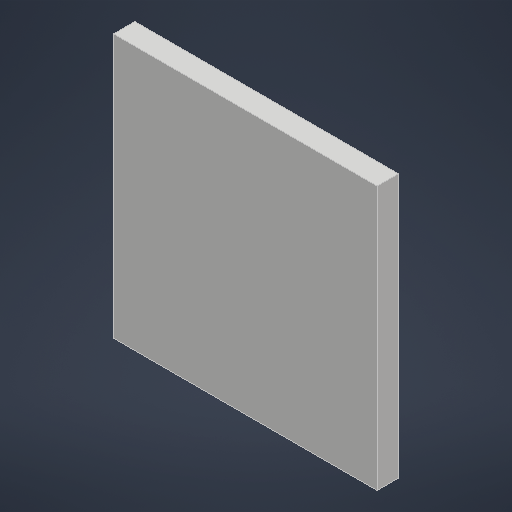
# Autodesk Inventor part: Marble Maze Template
Saved by Autodesk Inventor 2027 (Build 310192060, 192F)
## iProperties
Created: 2021-01-22
Part Number: Marble Maze Template
Material: Generic
Document SubType Name: Modeling
Designer: ScottSt
Density: 1 g/cm^3
Appearance: Default
Author: ScottSt
Autodesk Inventor part; units mm, degrees
ref_plane "YZ Plane" through (0, 0, 0) normal (1, 0, 0) x (0, 1, 0)
ref_plane "XZ Plane" through (0, 0, 0) normal (0, 1, 0) x (-1, 0, 0)
ref_plane "XY Plane" through (0, 0, 0) normal (0, 0, 1) x (1, 0, 0)
sketch "Sketch1" plane through (0, 0, 0) normal (0, 1, 0) x (-1, 0, 0)
  line L0 (83.5, -83.5) -> (-83.5, -83.5)
  line L1 (-83.5, -83.5) -> (-83.5, 83.5)
  line L2 (-83.5, 83.5) -> (83.5, 83.5)
  line L3 (83.5, 83.5) -> (83.5, -83.5)
  line L4 (83.5, -83.5) -> (-83.5, 83.5) construction
  line L5 (-83.5, -83.5) -> (83.5, 83.5) construction
  point P0 (0, 0)
  dimension "d6" = 167
  dimension "d7" = 167
  constraints: 12 end point, 2 midpoint, 2 parallel, 1 horizontal, 1 perpendicular
  measures "d6" distance of L1.end L2.end
  measures "d7" distance of L0.end L1.end
extrude "Extrusion3" add sketch "Sketch1" along normal blind 3.5
sketch "Maze Layout" plane through (0, 3.5, 0) normal (0, 1, 0) x (1, 0, 0)
  line L0 (83.5, 83.5) -> (-83.5, 83.5) construction
  line L1 (83.5, -83.5) -> (83.5, 83.5) construction
  line L2 (-83.5, 83.5) -> (83.5, 83.5) construction
  line L3 (83.5, 83.5) -> (83.5, -83.5) construction
  line L4 (-80.5, -80.5) -> (80.5, -80.5) construction
  line L5 (80.5, -80.5) -> (80.5, 80.5) construction
  line L6 (80.5, 80.5) -> (-80.5, 80.5) construction
  line L7 (-80.5, 80.5) -> (-80.5, -80.5) construction
  line L8 (-80.5, -80.5) -> (-83.5, -80.5) construction
  line L9 (-83.5, -80.5) -> (-80.5, -80.5) construction
  line L10 (-80.5, -80.5) -> (-80.5, -83.5) construction
  line L11 (-83.5, -80.5) -> (-83.5, 80.5) construction
  line L12 (-83.5, 83.5) -> (-83.5, -83.5) construction
  line L13 (-83.5, 80.5) -> (-80.5, 80.5) construction
  line L14 (-60, 80.5) -> (-60, -80.5) construction
  line L15 (-63, -80.5) -> (-63, 80.5) construction
  line L16 (-63, 80.5) -> (-60, 80.5) construction
  line L17 (-60, -80.5) -> (-63, -80.5) construction
  line L18 (-39.5, 80.5) -> (-39.5, -80.5) construction
  line L19 (-42.5, -80.5) -> (-42.5, 80.5) construction
  line L20 (-42.5, 80.5) -> (-39.5, 80.5) construction
  line L21 (-39.5, -80.5) -> (-42.5, -80.5) construction
  line L22 (-19, 80.5) -> (-19, -80.5) construction
  line L23 (-22, -80.5) -> (-22, 80.5) construction
  line L24 (-22, 80.5) -> (-19, 80.5) construction
  line L25 (-19, -80.5) -> (-22, -80.5) construction
  line L26 (1.5, 80.5) -> (1.5, -80.5) construction
  line L27 (-1.5, -80.5) -> (-1.5, 80.5) construction
  line L28 (-1.5, 80.5) -> (1.5, 80.5) construction
  line L29 (1.5, -80.5) -> (-1.5, -80.5) construction
  line L30 (22, 80.5) -> (22, -80.5) construction
  line L31 (19, -80.5) -> (19, 80.5) construction
  line L32 (19, 80.5) -> (22, 80.5) construction
  line L33 (22, -80.5) -> (19, -80.5) construction
  line L34 (42.5, 80.5) -> (42.5, -80.5) construction
  line L35 (39.5, -80.5) -> (39.5, 80.5) construction
  line L36 (39.5, 80.5) -> (42.5, 80.5) construction
  line L37 (42.5, -80.5) -> (39.5, -80.5) construction
  line L38 (63, 80.5) -> (63, -80.5) construction
  line L39 (60, -80.5) -> (60, 80.5) construction
  line L40 (60, 80.5) -> (63, 80.5) construction
  line L41 (63, -80.5) -> (60, -80.5) construction
  line L42 (-80.5, -83.5) -> (80.5, -83.5) construction
  line L43 (80.5, -83.5) -> (80.5, -80.5) construction
  line L44 (-80.5, -60) -> (-80.5, -63) construction
  line L45 (-80.5, -60) -> (80.5, -60) construction
  line L46 (-80.5, -63) -> (80.5, -63) construction
  line L47 (80.5, -63) -> (80.5, -60) construction
  line L48 (-80.5, -39.5) -> (-80.5, -42.5) construction
  line L49 (-80.5, -39.5) -> (80.5, -39.5) construction
  line L50 (-80.5, -42.5) -> (80.5, -42.5) construction
  line L51 (80.5, -42.5) -> (80.5, -39.5) construction
  line L52 (-80.5, -19) -> (-80.5, -22) construction
  line L53 (-80.5, -19) -> (80.5, -19) construction
  line L54 (-80.5, -22) -> (80.5, -22) construction
  line L55 (80.5, -22) -> (80.5, -19) construction
  line L56 (-80.5, 1.5) -> (-80.5, -1.5) construction
  line L57 (-80.5, 1.5) -> (80.5, 1.5) construction
  line L58 (-80.5, -1.5) -> (80.5, -1.5) construction
  line L59 (80.5, -1.5) -> (80.5, 1.5) construction
  line L60 (-80.5, 22) -> (-80.5, 19) construction
  line L61 (-80.5, 22) -> (80.5, 22) construction
  line L62 (-80.5, 19) -> (80.5, 19) construction
  line L63 (80.5, 19) -> (80.5, 22) construction
  line L64 (-80.5, 42.5) -> (-80.5, 39.5) construction
  line L65 (-80.5, 42.5) -> (80.5, 42.5) construction
  line L66 (-80.5, 39.5) -> (80.5, 39.5) construction
  line L67 (80.5, 39.5) -> (80.5, 42.5) construction
  line L68 (-80.5, 63) -> (-80.5, 60) construction
  line L69 (-80.5, 63) -> (80.5, 63) construction
  line L70 (-80.5, 60) -> (80.5, 60) construction
  line L71 (80.5, 60) -> (80.5, 63) construction
  line L72 (42.5, 80.5) -> (39.5, 80.5)
  line L73 (22, 80.5) -> (19, 80.5)
  line L74 (-22, 80.5) -> (-19, 80.5)
  line L75 (-80.5, 60) -> (-80.5, 63)
  line L76 (80.5, 60) -> (80.5, 63)
  line L77 (80.5, 1.5) -> (80.5, -1.5)
  line L78 (63, -80.5) -> (60, -80.5)
  line L79 (22, -80.5) -> (19, -80.5)
  line L80 (-39.5, -80.5) -> (-42.5, -80.5)
  line L81 (-80.5, -60) -> (-80.5, -63)
  line L82 (-80.5, -19) -> (-80.5, -22)
  line L83 (83.5, -83.5) -> (-83.5, -83.5)
  line L84 (-83.5, -83.5) -> (-83.5, 83.5)
  line L85 (-83.5, 83.5) -> (83.5, 83.5)
  line L86 (83.5, 83.5) -> (83.5, -83.5)
  line L87 (-80.5, 80.5) -> (80.5, 80.5)
  line L88 (80.5, 80.5) -> (80.5, -80.5)
  line L89 (80.5, -80.5) -> (-80.5, -80.5)
  line L90 (-80.5, -80.5) -> (-80.5, 80.5)
  line L91 (-80.5, -60) -> (-63, -60)
  line L92 (-63, -60) -> (-63, -42.5)
  line L93 (-63, -42.5) -> (-63, -39.5)
  line L94 (-63, -39.5) -> (-63, 1.5)
  line L95 (-63, 1.5) -> (-39.5, 1.5)
  line L96 (-39.5, 1.5) -> (-39.5, -63)
  line L97 (-39.5, -63) -> (-42.5, -63)
  line L98 (-42.5, -63) -> (-42.5, -1.5)
  line L99 (-42.5, -1.5) -> (-60, -1.5)
  line L100 (-60, -1.5) -> (-60, -63)
  line L101 (-60, -63) -> (-80.5, -63)
  line L102 (-80.5, -63) -> (-80.5, -60)
  line L103 (-22, -63) -> (22, -63)
  line L104 (22, -63) -> (22, -60)
  line L105 (22, -60) -> (-22, -60)
  line L106 (-22, -63) -> (-22, -60)
  line L107 (19, -63) -> (19, -80.5)
  line L108 (19, -80.5) -> (22, -80.5)
  line L109 (22, -80.5) -> (22, -63)
  line L110 (-22, -42.5) -> (39.5, -42.5)
  line L111 (39.5, -42.5) -> (39.5, -63)
  line L112 (39.5, -63) -> (63, -63)
  line L113 (63, -63) -> (63, 1.5)
  line L114 (63, 1.5) -> (1.5, 1.5)
  line L115 (1.5, 1.5) -> (1.5, 19)
  line L116 (1.5, 22) -> (1.5, 19)
  line L117 (1.5, 22) -> (-19, 22)
  line L118 (-19, 39.5) -> (39.5, 39.5)
  line L119 (39.5, 39.5) -> (39.5, 19)
  line L120 (39.5, 19) -> (63, 19)
  line L121 (63, 19) -> (63, 80.5)
  line L122 (63, 80.5) -> (60, 80.5)
  line L123 (60, 80.5) -> (60, 22)
  line L124 (60, 22) -> (42.5, 22)
  line L125 (42.5, 22) -> (42.5, 42.5)
  line L126 (42.5, 42.5) -> (-22, 42.5)
  line L127 (-22, 19) -> (-1.5, 19)
  line L128 (-1.5, 19) -> (-1.5, -1.5)
  line L129 (-1.5, -1.5) -> (60, -1.5)
  line L130 (60, -1.5) -> (60, -60)
  line L131 (60, -60) -> (42.5, -60)
  line L132 (42.5, -60) -> (42.5, -39.5)
  line L133 (42.5, -39.5) -> (-22, -39.5)
  line L134 (-22, -39.5) -> (-22, -42.5)
  line L135 (-1.5, -39.5) -> (-1.5, -22)
  line L136 (-1.5, -22) -> (1.5, -22)
  line L137 (1.5, -22) -> (1.5, -39.5)
  line L138 (19, -1.5) -> (19, -19)
  line L139 (19, -19) -> (22, -19)
  line L140 (22, -19) -> (22, -1.5)
  line L141 (39.5, -39.5) -> (39.5, -22)
  line L142 (39.5, -22) -> (42.5, -22)
  line L143 (42.5, -22) -> (42.5, -39.5)
  line L144 (-19, 22) -> (-22, 22)
  line L145 (-22, 22) -> (-22, 19)
  line L146 (-22, 39.5) -> (-22, 42.5)
  line L147 (-19, 39.5) -> (-22, 39.5)
  line L148 (63, -1.5) -> (80.5, -1.5)
  line L149 (80.5, -1.5) -> (80.5, 1.5)
  line L150 (80.5, 1.5) -> (63, 1.5)
  line L151 (19, 1.5) -> (19, 19)
  line L152 (19, 19) -> (22, 19)
  line L153 (22, 19) -> (22, 1.5)
  line L154 (-60, 80.5) -> (-60, 22)
  line L155 (-60, 22) -> (-42.5, 22)
  line L156 (-42.5, 22) -> (-42.5, 80.5)
  line L157 (-42.5, 80.5) -> (-39.5, 80.5)
  line L158 (-39.5, 80.5) -> (-39.5, 19)
  line L159 (-39.5, 19) -> (-63, 19)
  line L160 (-63, 19) -> (-63, 80.5)
  line L161 (60, 60) -> (-1.5, 60)
  line L162 (-1.5, 60) -> (-1.5, 63)
  line L163 (-1.5, 63) -> (60, 63)
  line L164 (-63, 80.5) -> (-60, 80.5)
  line L165 (-42.5, 80.5) -> (-39.5, 80.5)
  line L166 (-80.5, -60) -> (-80.5, -63)
  line L167 (19, -80.5) -> (22, -80.5)
  line L168 (80.5, 1.5) -> (80.5, -1.5)
  line L169 (60, 80.5) -> (63, 80.5)
  dimension "d25" = 20.5
  dimension "d32" = 20.5
  constraints: 326 end point, 103 point on line, 20 perpendicular, 15 collinear, 11 horizontal, 7 parallel, 4 vertical, 148 other
  measures "d25" distance of L6.end L14.start
  measures "d32" distance of L4.start L44.start
extrude "Extrusion5" add sketch "Maze Layout" along normal blind 10 contours L87 L121 L120 L119 L118 L147 L146 L126 L125 L124 L123 | L123 L161 L162 L163 | L158 L159 L160 L87 L154 L155 L156 | L77 L148 L113 L150 | L113 L112 L111 L110 L134 L133 L132 L131 L130 L129 L128 L127 L145 L144 L117 L116 L115 L114 | L114 L151 L152 L153 | L79 L107 L103 L109 | L103 L106 L105 L104 | L135 L136 L137 L133 | L91 L92 L93 L94 L95 L96 L97 L98 L99 L100 L101 L81 | L141 L142 L143 L133 | L129 L140 L139 L138 | L83 L84 L85 L86
body "Solid3"
